DSCaseIUpperSide (Autodesk Fusion 360 design; units mm, degrees)
Autodesk Fusion 360 part; units mm, degrees
sketch "Sketch1" plane through (0, 0, 0) normal (0, 0, 1) x (1, 0, 0)
  line L0 (13.5, -13.5) -> (-13.5, -13.5)
  line L1 (-13.5, -13.5) -> (-13.5, 13.5)
  line L2 (-13.5, 13.5) -> (13.5, 13.5)
  line L3 (13.5, 13.5) -> (13.5, -13.5)
  line L4 (13.5, -13.5) -> (-13.5, 13.5) construction
  line L5 (-13.5, -13.5) -> (13.5, 13.5) construction
  dimension "d1" = 27
  dimension "d2" = 27
  constraint perpendicular L0 L1
  constraint parallel L0 L2
  constraint parallel L1 L3
  constraint horizontal L0
  constraint coincident L4 origin
  constraint coincident L5 origin
  measures "d1" distance of L1.end L2.end
  measures "d2" distance of L0.end L1.end
extrude "Extrude1" add sketch "Sketch1" along normal blind 2
sketch "Sketch2" plane through (0, 0, 2) normal (0, 0, 1) x (1, 0, 0)
  line L0 (13.5, 13.5) -> (-13.5, 13.5)
  line L1 (-13.5, 13.5) -> (-13.5, -13.5)
  line L2 (-13.5, -13.5) -> (13.5, -13.5)
  line L3 (13.5, -13.5) -> (13.5, 13.5)
  line L4 (13.5, -13.5) -> (-11.5, -13.5)
  line L5 (-11.5, -13.5) -> (-11.5, 11.5)
  line L6 (-11.5, 11.5) -> (13.5, 11.5)
  line L7 (13.5, 11.5) -> (13.5, -13.5)
  dimension "d5" = 25
  dimension "d6" = 25
  constraint horizontal L4
  constraint vertical L5
  constraint horizontal L6
  constraint vertical L7
  constraint coincident L2.end L3.start
  measures "d5" distance of L2.end L6.end
  measures "d6" distance of L2.end L4.end
extrude "Extrude2" add sketch "Sketch2" along normal blind 16 contours L0 L1 L2 L3 L5 L6
sketch "Sketch3" plane through (0, 0, 18) normal (0, 0, 1) x (1, 0, 0)
  line L0 (-11.5, 11.5) -> (13.5, 11.5)
  line L1 (13.5, 11.5) -> (13.5, 13.5)
  line L2 (13.5, 13.5) -> (-13.5, 13.5)
  line L3 (-13.5, 13.5) -> (-13.5, -13.5)
  line L4 (-13.5, -13.5) -> (-11.5, -13.5)
  line L5 (-11.5, -13.5) -> (-11.5, 11.5)
  line L6 (-13.5, 13.5) -> (13.5, 13.5)
  line L7 (13.5, 13.5) -> (13.5, -13.5)
  line L8 (13.5, -13.5) -> (-13.5, -13.5)
  line L9 (-13.5, -13.5) -> (-13.5, 13.5)
  point P0 (13.5, -13.5)
  constraint horizontal L6
  constraint vertical L7
  constraint horizontal L8
  constraint vertical L9
  constraint coincident P0 L7.end
  constraint coincident L2.end L3.start
extrude "Extrude3" add sketch "Sketch3" along normal blind 2
sketch "Sketch5" plane through (13.5, 0, 0) normal (1, 0, 0) x (0, 0, -1)
  line L0 (0, -13.5) -> (0, 13.5)
  line L1 (0, 13.5) -> (-20, 13.5)
  line L2 (-20, 13.5) -> (-20, -13.5)
  line L3 (-20, -13.5) -> (-18, -13.5)
  line L4 (-18, -13.5) -> (-18, 11.5)
  line L5 (-18, 11.5) -> (-2, 11.5)
  line L6 (-2, 11.5) -> (-2, -13.5)
  line L7 (-2, -13.5) -> (0, -13.5)
  line L8 (-10.5, 13.5) -> (-9.5, 13.5)
  line L9 (-8.954, 12) -> (-11.046, 12)
  line L10 (-11.046, 12) -> (-10.5, 13.5)
  line L11 (-9.5, 13.5) -> (-8.954, 12)
sketch "Sketch6" plane through (0, -13.5, 0) normal (0, -1, 0) x (1, 0, 0)
  line L0 (-13.5, 0) -> (13.5, 0)
  line L1 (13.5, 0) -> (13.5, 2)
  line L2 (13.5, 2) -> (-11.5, 2)
  line L3 (-11.5, 2) -> (-11.5, 18)
  line L4 (-11.5, 18) -> (13.5, 18)
  line L5 (13.5, 18) -> (13.5, 20)
  line L6 (13.5, 20) -> (-13.5, 20)
  line L7 (-13.5, 20) -> (-13.5, 0)
  line L8 (0, 0) -> (0.5, 0)
  line L9 (1.625, 1.5) -> (0.5, 0)
  line L10 (0.5, 0) -> (-0.5, 0)
  line L11 (-0.5, 0) -> (-1.625, 1.5)
  line L12 (-1.625, 1.5) -> (1.625, 1.5)
  line L13 (-1.625, 21.5) -> (-0.5, 20)
  line L14 (-0.5, 20) -> (0.5, 20)
  line L15 (0.5, 20) -> (1.625, 21.5)
  line L16 (1.625, 21.5) -> (-1.625, 21.5)
  constraint coincident L8.start origin
  constraint horizontal L8
extrude "Extrude6" cut sketch "Sketch6" against normal blind 10 contours L0 L8 L9 L10 L11 L12
extrude "Extrude7" add sketch "Sketch6" against normal blind 10 contours L6 L13 L14 L15 L16
sketch "Sketch7" plane through (9.28, 0, 6.96) normal (-0.8, 0, -0.6) x (-0.6, 0, 0.8)
  line L0 (16.3, -13.5) -> (18.175, -13.5)
  line L1 (18.175, -13.5) -> (18.175, -3.5)
  line L2 (18.175, -3.5) -> (16.3, -3.5)
  line L3 (16.3, -3.5) -> (16.3, -13.5)
extrude "Extrude8" cut sketch "Sketch7" against normal blind 0.1
sketch "Sketch8" plane through (-9.28, 0, 6.96) normal (0.8, 0, -0.6) x (-0.6, 0, -0.8)
  line L0 (-18.175, -13.5) -> (-16.3, -13.5)
  line L1 (-16.3, -13.5) -> (-16.3, -3.5)
  line L2 (-16.3, -3.5) -> (-18.175, -3.5)
  line L3 (-18.175, -3.5) -> (-18.175, -13.5)
extrude "Extrude9" cut sketch "Sketch8" against normal blind 0.1
sketch "Sketch9" plane through (0, 0, 21.5) normal (0, 0, 1) x (1, 0, 0)
  line L0 (1.5, -13.5) -> (1.5, -3.5)
  line L1 (1.5, -3.5) -> (-1.5, -3.5)
  line L2 (-1.5, -3.5) -> (-1.5, -13.5)
  line L3 (-1.5, -13.5) -> (1.5, -13.5)
extrude "Extrude10" cut sketch "Sketch9" against normal blind 0.1
